Autodesk Fusion 360 part; units mm, degrees
(part 5 of 7)
equation "d238 = abs(( 0 ) * ( ( ( 1 ) * jointNodeQ * sqrt(2) - bodyWidth / 2 * cos(225 deg) + ( ( -1 ) * nodeHalfWidth ) * sin(225 deg) ) + ( 0 ) * ( ( 1 ) * endNodeX - ( ( 1 ) * jointNodeQ * sqrt(2) - bodyWidth / 2 * cos(225 deg) + ( ( -1 ) * nodeHalfWidth ) * sin(225 deg) ) ) ) + ( -1 ) * ( ( -1 ) * nodeHalfWidth ))"
equation "d239 = abs(( 1 ) * ( ( ( 1 ) * jointNodeQ * sqrt(2) - bodyWidth / 2 * cos(225 deg) + ( ( 1 ) * nodeHalfWidth ) * sin(225 deg) ) + ( 0 ) * ( ( 1 ) * endNodeX - ( ( 1 ) * jointNodeQ * sqrt(2) - bodyWidth / 2 * cos(225 deg) + ( ( 1 ) * nodeHalfWidth ) * sin(225 deg) ) ) ) + ( 0 ) * ( ( 1 ) * nodeHalfWidth ))"
equation "d240 = abs(( 0 ) * ( ( ( 1 ) * jointNodeQ * sqrt(2) - bodyWidth / 2 * cos(225 deg) + ( ( 1 ) * nodeHalfWidth ) * sin(225 deg) ) + ( 0 ) * ( ( 1 ) * endNodeX - ( ( 1 ) * jointNodeQ * sqrt(2) - bodyWidth / 2 * cos(225 deg) + ( ( 1 ) * nodeHalfWidth ) * sin(225 deg) ) ) ) + ( -1 ) * ( ( 1 ) * nodeHalfWidth ))"
equation "d241 = abs(( 1 ) * ( ( ( 1 ) * jointNodeQ * sqrt(2) - bodyWidth / 2 * cos(225 deg) + ( ( -1 ) * nodeHalfWidth ) * sin(225 deg) ) + ( 1 ) * ( ( 1 ) * endNodeX - ( ( 1 ) * jointNodeQ * sqrt(2) - bodyWidth / 2 * cos(225 deg) + ( ( -1 ) * nodeHalfWidth ) * sin(225 deg) ) ) ) + ( 0 ) * ( ( -1 ) * nodeHalfWidth ))"
equation "d242 = abs(( 0 ) * ( ( ( 1 ) * jointNodeQ * sqrt(2) - bodyWidth / 2 * cos(225 deg) + ( ( -1 ) * nodeHalfWidth ) * sin(225 deg) ) + ( 1 ) * ( ( 1 ) * endNodeX - ( ( 1 ) * jointNodeQ * sqrt(2) - bodyWidth / 2 * cos(225 deg) + ( ( -1 ) * nodeHalfWidth ) * sin(225 deg) ) ) ) + ( -1 ) * ( ( -1 ) * nodeHalfWidth ))"
equation "d243 = -memberWidth / 2"
equation "d244 = -( wall + 0.2 mm )"
equation "d246 = abs(( 1 ) * ( ( ( 1 ) * jointNodeQ * sqrt(2) - bodyWidth / 2 * cos(225 deg) + ( ( 1 ) * nodeHalfWidth ) * sin(225 deg) ) + ( 0 ) * ( ( 1 ) * endNodeX - ( ( 1 ) * jointNodeQ * sqrt(2) - bodyWidth / 2 * cos(225 deg) + ( ( 1 ) * nodeHalfWidth ) * sin(225 deg) ) ) ) + ( 0 ) * ( ( 1 ) * nodeHalfWidth ))"
equation "d247 = abs(( 0 ) * ( ( ( 1 ) * jointNodeQ * sqrt(2) - bodyWidth / 2 * cos(225 deg) + ( ( 1 ) * nodeHalfWidth ) * sin(225 deg) ) + ( 0 ) * ( ( 1 ) * endNodeX - ( ( 1 ) * jointNodeQ * sqrt(2) - bodyWidth / 2 * cos(225 deg) + ( ( 1 ) * nodeHalfWidth ) * sin(225 deg) ) ) ) + ( -1 ) * ( ( 1 ) * nodeHalfWidth ))"
equation "d248 = abs(( 1 ) * ( ( ( 1 ) * jointNodeQ * sqrt(2) - bodyWidth / 2 * cos(225 deg) + ( ( -1 ) * nodeHalfWidth ) * sin(225 deg) ) + ( 1 ) * ( ( 1 ) * endNodeX - ( ( 1 ) * jointNodeQ * sqrt(2) - bodyWidth / 2 * cos(225 deg) + ( ( -1 ) * nodeHalfWidth ) * sin(225 deg) ) ) ) + ( 0 ) * ( ( -1 ) * nodeHalfWidth ))"
equation "d249 = abs(( 0 ) * ( ( ( 1 ) * jointNodeQ * sqrt(2) - bodyWidth / 2 * cos(225 deg) + ( ( -1 ) * nodeHalfWidth ) * sin(225 deg) ) + ( 1 ) * ( ( 1 ) * endNodeX - ( ( 1 ) * jointNodeQ * sqrt(2) - bodyWidth / 2 * cos(225 deg) + ( ( -1 ) * nodeHalfWidth ) * sin(225 deg) ) ) ) + ( -1 ) * ( ( -1 ) * nodeHalfWidth ))"
equation "d250 = abs(( 1 ) * ( ( ( 1 ) * jointNodeQ * sqrt(2) - bodyWidth / 2 * cos(225 deg) + ( ( 1 ) * nodeHalfWidth ) * sin(225 deg) ) + ( 1 ) * ( ( 1 ) * endNodeX - ( ( 1 ) * jointNodeQ * sqrt(2) - bodyWidth / 2 * cos(225 deg) + ( ( 1 ) * nodeHalfWidth ) * sin(225 deg) ) ) ) + ( 0 ) * ( ( 1 ) * nodeHalfWidth ))"
equation "d251 = abs(( 0 ) * ( ( ( 1 ) * jointNodeQ * sqrt(2) - bodyWidth / 2 * cos(225 deg) + ( ( 1 ) * nodeHalfWidth ) * sin(225 deg) ) + ( 1 ) * ( ( 1 ) * endNodeX - ( ( 1 ) * jointNodeQ * sqrt(2) - bodyWidth / 2 * cos(225 deg) + ( ( 1 ) * nodeHalfWidth ) * sin(225 deg) ) ) ) + ( -1 ) * ( ( 1 ) * nodeHalfWidth ))"
equation "d252 = memberWidth / 2"
equation "d253 = -( wall + 0.2 mm )"
equation "d256 = apertureRadius"
equation "d259 = bodyWidth / 2"
equation "d261 = abs(( -1 ) * ( ( ( 1 ) * jointNodeQ * sqrt(2) - bodyWidth / 2 * cos(270 deg) + ( ( -1 ) * nodeHalfWidth ) * sin(270 deg) ) + ( 0 ) * ( ( 1 ) * endNodeX - ( ( 1 ) * jointNodeQ * sqrt(2) - bodyWidth / 2 * cos(270 deg) + ( ( -1 ) * nodeHalfWidth ) * sin(270 deg) ) ) ) + ( 0 ) * ( ( -1 ) * nodeHalfWidth ))"
equation "d262 = abs(( 0 ) * ( ( ( 1 ) * jointNodeQ * sqrt(2) - bodyWidth / 2 * cos(270 deg) + ( ( -1 ) * nodeHalfWidth ) * sin(270 deg) ) + ( 0 ) * ( ( 1 ) * endNodeX - ( ( 1 ) * jointNodeQ * sqrt(2) - bodyWidth / 2 * cos(270 deg) + ( ( -1 ) * nodeHalfWidth ) * sin(270 deg) ) ) ) + ( 1 ) * ( ( -1 ) * nodeHalfWidth ))"
equation "d263 = abs(( -1 ) * ( ( ( 1 ) * jointNodeQ * sqrt(2) - bodyWidth / 2 * cos(270 deg) + ( ( 1 ) * nodeHalfWidth ) * sin(270 deg) ) + ( 0 ) * ( ( 1 ) * endNodeX - ( ( 1 ) * jointNodeQ * sqrt(2) - bodyWidth / 2 * cos(270 deg) + ( ( 1 ) * nodeHalfWidth ) * sin(270 deg) ) ) ) + ( 0 ) * ( ( 1 ) * nodeHalfWidth ))"
equation "d264 = abs(( 0 ) * ( ( ( 1 ) * jointNodeQ * sqrt(2) - bodyWidth / 2 * cos(270 deg) + ( ( 1 ) * nodeHalfWidth ) * sin(270 deg) ) + ( 0 ) * ( ( 1 ) * endNodeX - ( ( 1 ) * jointNodeQ * sqrt(2) - bodyWidth / 2 * cos(270 deg) + ( ( 1 ) * nodeHalfWidth ) * sin(270 deg) ) ) ) + ( 1 ) * ( ( 1 ) * nodeHalfWidth ))"
equation "d265 = abs(( -1 ) * ( ( ( 1 ) * jointNodeQ * sqrt(2) - bodyWidth / 2 * cos(270 deg) + ( ( -1 ) * nodeHalfWidth ) * sin(270 deg) ) + ( 0.5 ) * ( ( 1 ) * endNodeX - ( ( 1 ) * jointNodeQ * sqrt(2) - bodyWidth / 2 * cos(270 deg) + ( ( -1 ) * nodeHalfWidth ) * sin(270 deg) ) ) ) + ( 0 ) * ( ( -1 ) * nodeHalfWidth ))"
equation "d266 = abs(( 0 ) * ( ( ( 1 ) * jointNodeQ * sqrt(2) - bodyWidth / 2 * cos(270 deg) + ( ( -1 ) * nodeHalfWidth ) * sin(270 deg) ) + ( 0.5 ) * ( ( 1 ) * endNodeX - ( ( 1 ) * jointNodeQ * sqrt(2) - bodyWidth / 2 * cos(270 deg) + ( ( -1 ) * nodeHalfWidth ) * sin(270 deg) ) ) ) + ( 1 ) * ( ( -1 ) * nodeHalfWidth ))"
equation "d267 = -memberWidth / 2"
equation "d268 = -( wall + 0.2 mm )"
equation "d270 = abs(( -1 ) * ( ( ( 1 ) * jointNodeQ * sqrt(2) - bodyWidth / 2 * cos(270 deg) + ( ( 1 ) * nodeHalfWidth ) * sin(270 deg) ) + ( 0 ) * ( ( 1 ) * endNodeX - ( ( 1 ) * jointNodeQ * sqrt(2) - bodyWidth / 2 * cos(270 deg) + ( ( 1 ) * nodeHalfWidth ) * sin(270 deg) ) ) ) + ( 0 ) * ( ( 1 ) * nodeHalfWidth ))"
equation "d271 = abs(( 0 ) * ( ( ( 1 ) * jointNodeQ * sqrt(2) - bodyWidth / 2 * cos(270 deg) + ( ( 1 ) * nodeHalfWidth ) * sin(270 deg) ) + ( 0 ) * ( ( 1 ) * endNodeX - ( ( 1 ) * jointNodeQ * sqrt(2) - bodyWidth / 2 * cos(270 deg) + ( ( 1 ) * nodeHalfWidth ) * sin(270 deg) ) ) ) + ( 1 ) * ( ( 1 ) * nodeHalfWidth ))"
equation "d272 = abs(( -1 ) * ( ( ( 1 ) * jointNodeQ * sqrt(2) - bodyWidth / 2 * cos(270 deg) + ( ( -1 ) * nodeHalfWidth ) * sin(270 deg) ) + ( 0.5 ) * ( ( 1 ) * endNodeX - ( ( 1 ) * jointNodeQ * sqrt(2) - bodyWidth / 2 * cos(270 deg) + ( ( -1 ) * nodeHalfWidth ) * sin(270 deg) ) ) ) + ( 0 ) * ( ( -1 ) * nodeHalfWidth ))"
equation "d273 = abs(( 0 ) * ( ( ( 1 ) * jointNodeQ * sqrt(2) - bodyWidth / 2 * cos(270 deg) + ( ( -1 ) * nodeHalfWidth ) * sin(270 deg) ) + ( 0.5 ) * ( ( 1 ) * endNodeX - ( ( 1 ) * jointNodeQ * sqrt(2) - bodyWidth / 2 * cos(270 deg) + ( ( -1 ) * nodeHalfWidth ) * sin(270 deg) ) ) ) + ( 1 ) * ( ( -1 ) * nodeHalfWidth ))"
equation "d274 = abs(( -1 ) * ( ( ( 1 ) * jointNodeQ * sqrt(2) - bodyWidth / 2 * cos(270 deg) + ( ( 1 ) * nodeHalfWidth ) * sin(270 deg) ) + ( 1 ) * ( ( 1 ) * endNodeX - ( ( 1 ) * jointNodeQ * sqrt(2) - bodyWidth / 2 * cos(270 deg) + ( ( 1 ) * nodeHalfWidth ) * sin(270 deg) ) ) ) + ( 0 ) * ( ( 1 ) * nodeHalfWidth ))"
equation "d275 = abs(( 0 ) * ( ( ( 1 ) * jointNodeQ * sqrt(2) - bodyWidth / 2 * cos(270 deg) + ( ( 1 ) * nodeHalfWidth ) * sin(270 deg) ) + ( 1 ) * ( ( 1 ) * endNodeX - ( ( 1 ) * jointNodeQ * sqrt(2) - bodyWidth / 2 * cos(270 deg) + ( ( 1 ) * nodeHalfWidth ) * sin(270 deg) ) ) ) + ( 1 ) * ( ( 1 ) * nodeHalfWidth ))"
equation "d276 = memberWidth / 2"
equation "d277 = -( wall + 0.2 mm )"
equation "d279 = abs(( -1 ) * ( ( ( 1 ) * jointNodeQ * sqrt(2) - bodyWidth / 2 * cos(270 deg) + ( ( -1 ) * nodeHalfWidth ) * sin(270 deg) ) + ( 0.5 ) * ( ( 1 ) * endNodeX - ( ( 1 ) * jointNodeQ * sqrt(2) - bodyWidth / 2 * cos(270 deg) + ( ( -1 ) * nodeHalfWidth ) * sin(270 deg) ) ) ) + ( 0 ) * ( ( -1 ) * nodeHalfWidth ))"
equation "d280 = abs(( 0 ) * ( ( ( 1 ) * jointNodeQ * sqrt(2) - bodyWidth / 2 * cos(270 deg) + ( ( -1 ) * nodeHalfWidth ) * sin(270 deg) ) + ( 0.5 ) * ( ( 1 ) * endNodeX - ( ( 1 ) * jointNodeQ * sqrt(2) - bodyWidth / 2 * cos(270 deg) + ( ( -1 ) * nodeHalfWidth ) * sin(270 deg) ) ) ) + ( 1 ) * ( ( -1 ) * nodeHalfWidth ))"
equation "d281 = abs(( -1 ) * ( ( ( 1 ) * jointNodeQ * sqrt(2) - bodyWidth / 2 * cos(270 deg) + ( ( 1 ) * nodeHalfWidth ) * sin(270 deg) ) + ( 1 ) * ( ( 1 ) * endNodeX - ( ( 1 ) * jointNodeQ * sqrt(2) - bodyWidth / 2 * cos(270 deg) + ( ( 1 ) * nodeHalfWidth ) * sin(270 deg) ) ) ) + ( 0 ) * ( ( 1 ) * nodeHalfWidth ))"
equation "d282 = abs(( 0 ) * ( ( ( 1 ) * jointNodeQ * sqrt(2) - bodyWidth / 2 * cos(270 deg) + ( ( 1 ) * nodeHalfWidth ) * sin(270 deg) ) + ( 1 ) * ( ( 1 ) * endNodeX - ( ( 1 ) * jointNodeQ * sqrt(2) - bodyWidth / 2 * cos(270 deg) + ( ( 1 ) * nodeHalfWidth ) * sin(270 deg) ) ) ) + ( 1 ) * ( ( 1 ) * nodeHalfWidth ))"
equation "d283 = abs(( -1 ) * ( ( ( 1 ) * jointNodeQ * sqrt(2) - bodyWidth / 2 * cos(270 deg) + ( ( -1 ) * nodeHalfWidth ) * sin(270 deg) ) + ( 1 ) * ( ( 1 ) * endNodeX - ( ( 1 ) * jointNodeQ * sqrt(2) - bodyWidth / 2 * cos(270 deg) + ( ( -1 ) * nodeHalfWidth ) * sin(270 deg) ) ) ) + ( 0 ) * ( ( -1 ) * nodeHalfWidth ))"
equation "d284 = abs(( 0 ) * ( ( ( 1 ) * jointNodeQ * sqrt(2) - bodyWidth / 2 * cos(270 deg) + ( ( -1 ) * nodeHalfWidth ) * sin(270 deg) ) + ( 1 ) * ( ( 1 ) * endNodeX - ( ( 1 ) * jointNodeQ * sqrt(2) - bodyWidth / 2 * cos(270 deg) + ( ( -1 ) * nodeHalfWidth ) * sin(270 deg) ) ) ) + ( 1 ) * ( ( -1 ) * nodeHalfWidth ))"
equation "d285 = -memberWidth / 2"
equation "d286 = -( wall + 0.2 mm )"
equation "d289 = apertureRadius"
equation "d292 = bodyWidth / 2"
equation "d294 = abs(( 1 ) * ( ( ( 1 ) * jointNodeQ * sqrt(2) - bodyWidth / 2 * cos(315 deg) + ( ( -1 ) * nodeHalfWidth ) * sin(315 deg) ) + ( 0 ) * ( ( 1 ) * endNodeX - ( ( 1 ) * jointNodeQ * sqrt(2) - bodyWidth / 2 * cos(315 deg) + ( ( -1 ) * nodeHalfWidth ) * sin(315 deg) ) ) ) + ( 0 ) * ( ( -1 ) * nodeHalfWidth ))"
equation "d295 = abs(( 0 ) * ( ( ( 1 ) * jointNodeQ * sqrt(2) - bodyWidth / 2 * cos(315 deg) + ( ( -1 ) * nodeHalfWidth ) * sin(315 deg) ) + ( 0 ) * ( ( 1 ) * endNodeX - ( ( 1 ) * jointNodeQ * sqrt(2) - bodyWidth / 2 * cos(315 deg) + ( ( -1 ) * nodeHalfWidth ) * sin(315 deg) ) ) ) + ( -1 ) * ( ( -1 ) * nodeHalfWidth ))"
equation "d296 = abs(( 1 ) * ( ( ( 1 ) * jointNodeQ * sqrt(2) - bodyWidth / 2 * cos(315 deg) + ( ( 1 ) * nodeHalfWidth ) * sin(315 deg) ) + ( 0 ) * ( ( 1 ) * endNodeX - ( ( 1 ) * jointNodeQ * sqrt(2) - bodyWidth / 2 * cos(315 deg) + ( ( 1 ) * nodeHalfWidth ) * sin(315 deg) ) ) ) + ( 0 ) * ( ( 1 ) * nodeHalfWidth ))"
equation "d297 = abs(( 0 ) * ( ( ( 1 ) * jointNodeQ * sqrt(2) - bodyWidth / 2 * cos(315 deg) + ( ( 1 ) * nodeHalfWidth ) * sin(315 deg) ) + ( 0 ) * ( ( 1 ) * endNodeX - ( ( 1 ) * jointNodeQ * sqrt(2) - bodyWidth / 2 * cos(315 deg) + ( ( 1 ) * nodeHalfWidth ) * sin(315 deg) ) ) ) + ( -1 ) * ( ( 1 ) * nodeHalfWidth ))"
equation "d298 = abs(( 1 ) * ( ( ( 1 ) * jointNodeQ * sqrt(2) - bodyWidth / 2 * cos(315 deg) + ( ( -1 ) * nodeHalfWidth ) * sin(315 deg) ) + ( 0.333333333333333 ) * ( ( 1 ) * endNodeX - ( ( 1 ) * jointNodeQ * sqrt(2) - bodyWidth / 2 * cos(315 deg) + ( ( -1 ) * nodeHalfWidth ) * sin(315 deg) ) ) ) + ( 0 ) * ( ( -1 ) * nodeHalfWidth ))"
equation "d299 = abs(( 0 ) * ( ( ( 1 ) * jointNodeQ * sqrt(2) - bodyWidth / 2 * cos(315 deg) + ( ( -1 ) * nodeHalfWidth ) * sin(315 deg) ) + ( 0.333333333333333 ) * ( ( 1 ) * endNodeX - ( ( 1 ) * jointNodeQ * sqrt(2) - bodyWidth / 2 * cos(315 deg) + ( ( -1 ) * nodeHalfWidth ) * sin(315 deg) ) ) ) + ( -1 ) * ( ( -1 ) * nodeHalfWidth ))"
equation "d300 = -memberWidth / 2"
equation "d301 = -( wall + 0.2 mm )"
equation "d303 = abs(( 1 ) * ( ( ( 1 ) * jointNodeQ * sqrt(2) - bodyWidth / 2 * cos(315 deg) + ( ( 1 ) * nodeHalfWidth ) * sin(315 deg) ) + ( 0 ) * ( ( 1 ) * endNodeX - ( ( 1 ) * jointNodeQ * sqrt(2) - bodyWidth / 2 * cos(315 deg) + ( ( 1 ) * nodeHalfWidth ) * sin(315 deg) ) ) ) + ( 0 ) * ( ( 1 ) * nodeHalfWidth ))"
equation "d304 = abs(( 0 ) * ( ( ( 1 ) * jointNodeQ * sqrt(2) - bodyWidth / 2 * cos(315 deg) + ( ( 1 ) * nodeHalfWidth ) * sin(315 deg) ) + ( 0 ) * ( ( 1 ) * endNodeX - ( ( 1 ) * jointNodeQ * sqrt(2) - bodyWidth / 2 * cos(315 deg) + ( ( 1 ) * nodeHalfWidth ) * sin(315 deg) ) ) ) + ( -1 ) * ( ( 1 ) * nodeHalfWidth ))"
equation "d305 = abs(( 1 ) * ( ( ( 1 ) * jointNodeQ * sqrt(2) - bodyWidth / 2 * cos(315 deg) + ( ( -1 ) * nodeHalfWidth ) * sin(315 deg) ) + ( 0.333333333333333 ) * ( ( 1 ) * endNodeX - ( ( 1 ) * jointNodeQ * sqrt(2) - bodyWidth / 2 * cos(315 deg) + ( ( -1 ) * nodeHalfWidth ) * sin(315 deg) ) ) ) + ( 0 ) * ( ( -1 ) * nodeHalfWidth ))"
equation "d306 = abs(( 0 ) * ( ( ( 1 ) * jointNodeQ * sqrt(2) - bodyWidth / 2 * cos(315 deg) + ( ( -1 ) * nodeHalfWidth ) * sin(315 deg) ) + ( 0.333333333333333 ) * ( ( 1 ) * endNodeX - ( ( 1 ) * jointNodeQ * sqrt(2) - bodyWidth / 2 * cos(315 deg) + ( ( -1 ) * nodeHalfWidth ) * sin(315 deg) ) ) ) + ( -1 ) * ( ( -1 ) * nodeHalfWidth ))"
equation "d307 = abs(( 1 ) * ( ( ( 1 ) * jointNodeQ * sqrt(2) - bodyWidth / 2 * cos(315 deg) + ( ( 1 ) * nodeHalfWidth ) * sin(315 deg) ) + ( 0.666666666666667 ) * ( ( 1 ) * endNodeX - ( ( 1 ) * jointNodeQ * sqrt(2) - bodyWidth / 2 * cos(315 deg) + ( ( 1 ) * nodeHalfWidth ) * sin(315 deg) ) ) ) + ( 0 ) * ( ( 1 ) * nodeHalfWidth ))"
equation "d308 = abs(( 0 ) * ( ( ( 1 ) * jointNodeQ * sqrt(2) - bodyWidth / 2 * cos(315 deg) + ( ( 1 ) * nodeHalfWidth ) * sin(315 deg) ) + ( 0.666666666666667 ) * ( ( 1 ) * endNodeX - ( ( 1 ) * jointNodeQ * sqrt(2) - bodyWidth / 2 * cos(315 deg) + ( ( 1 ) * nodeHalfWidth ) * sin(315 deg) ) ) ) + ( -1 ) * ( ( 1 ) * nodeHalfWidth ))"
equation "d309 = memberWidth / 2"
equation "d310 = -( wall + 0.2 mm )"
equation "d312 = abs(( 1 ) * ( ( ( 1 ) * jointNodeQ * sqrt(2) - bodyWidth / 2 * cos(315 deg) + ( ( -1 ) * nodeHalfWidth ) * sin(315 deg) ) + ( 0.333333333333333 ) * ( ( 1 ) * endNodeX - ( ( 1 ) * jointNodeQ * sqrt(2) - bodyWidth / 2 * cos(315 deg) + ( ( -1 ) * nodeHalfWidth ) * sin(315 deg) ) ) ) + ( 0 ) * ( ( -1 ) * nodeHalfWidth ))"
equation "d313 = abs(( 0 ) * ( ( ( 1 ) * jointNodeQ * sqrt(2) - bodyWidth / 2 * cos(315 deg) + ( ( -1 ) * nodeHalfWidth ) * sin(315 deg) ) + ( 0.333333333333333 ) * ( ( 1 ) * endNodeX - ( ( 1 ) * jointNodeQ * sqrt(2) - bodyWidth / 2 * cos(315 deg) + ( ( -1 ) * nodeHalfWidth ) * sin(315 deg) ) ) ) + ( -1 ) * ( ( -1 ) * nodeHalfWidth ))"
equation "d314 = abs(( 1 ) * ( ( ( 1 ) * jointNodeQ * sqrt(2) - bodyWidth / 2 * cos(315 deg) + ( ( 1 ) * nodeHalfWidth ) * sin(315 deg) ) + ( 0.666666666666667 ) * ( ( 1 ) * endNodeX - ( ( 1 ) * jointNodeQ * sqrt(2) - bodyWidth / 2 * cos(315 deg) + ( ( 1 ) * nodeHalfWidth ) * sin(315 deg) ) ) ) + ( 0 ) * ( ( 1 ) * nodeHalfWidth ))"
equation "d315 = abs(( 0 ) * ( ( ( 1 ) * jointNodeQ * sqrt(2) - bodyWidth / 2 * cos(315 deg) + ( ( 1 ) * nodeHalfWidth ) * sin(315 deg) ) + ( 0.666666666666667 ) * ( ( 1 ) * endNodeX - ( ( 1 ) * jointNodeQ * sqrt(2) - bodyWidth / 2 * cos(315 deg) + ( ( 1 ) * nodeHalfWidth ) * sin(315 deg) ) ) ) + ( -1 ) * ( ( 1 ) * nodeHalfWidth ))"
equation "d316 = abs(( 1 ) * ( ( ( 1 ) * jointNodeQ * sqrt(2) - bodyWidth / 2 * cos(315 deg) + ( ( -1 ) * nodeHalfWidth ) * sin(315 deg) ) + ( 1 ) * ( ( 1 ) * endNodeX - ( ( 1 ) * jointNodeQ * sqrt(2) - bodyWidth / 2 * cos(315 deg) + ( ( -1 ) * nodeHalfWidth ) * sin(315 deg) ) ) ) + ( 0 ) * ( ( -1 ) * nodeHalfWidth ))"
equation "d317 = abs(( 0 ) * ( ( ( 1 ) * jointNodeQ * sqrt(2) - bodyWidth / 2 * cos(315 deg) + ( ( -1 ) * nodeHalfWidth ) * sin(315 deg) ) + ( 1 ) * ( ( 1 ) * endNodeX - ( ( 1 ) * jointNodeQ * sqrt(2) - bodyWidth / 2 * cos(315 deg) + ( ( -1 ) * nodeHalfWidth ) * sin(315 deg) ) ) ) + ( -1 ) * ( ( -1 ) * nodeHalfWidth ))"
equation "d318 = -memberWidth / 2"
equation "d319 = -( wall + 0.2 mm )"
equation "d321 = abs(( 1 ) * ( ( ( 1 ) * jointNodeQ * sqrt(2) - bodyWidth / 2 * cos(315 deg) + ( ( 1 ) * nodeHalfWidth ) * sin(315 deg) ) + ( 0.666666666666667 ) * ( ( 1 ) * endNodeX - ( ( 1 ) * jointNodeQ * sqrt(2) - bodyWidth / 2 * cos(315 deg) + ( ( 1 ) * nodeHalfWidth ) * sin(315 deg) ) ) ) + ( 0 ) * ( ( 1 ) * nodeHalfWidth ))"
equation "d322 = abs(( 0 ) * ( ( ( 1 ) * jointNodeQ * sqrt(2) - bodyWidth / 2 * cos(315 deg) + ( ( 1 ) * nodeHalfWidth ) * sin(315 deg) ) + ( 0.666666666666667 ) * ( ( 1 ) * endNodeX - ( ( 1 ) * jointNodeQ * sqrt(2) - bodyWidth / 2 * cos(315 deg) + ( ( 1 ) * nodeHalfWidth ) * sin(315 deg) ) ) ) + ( -1 ) * ( ( 1 ) * nodeHalfWidth ))"
equation "d323 = abs(( 1 ) * ( ( ( 1 ) * jointNodeQ * sqrt(2) - bodyWidth / 2 * cos(315 deg) + ( ( -1 ) * nodeHalfWidth ) * sin(315 deg) ) + ( 1 ) * ( ( 1 ) * endNodeX - ( ( 1 ) * jointNodeQ * sqrt(2) - bodyWidth / 2 * cos(315 deg) + ( ( -1 ) * nodeHalfWidth ) * sin(315 deg) ) ) ) + ( 0 ) * ( ( -1 ) * nodeHalfWidth ))"
equation "d324 = abs(( 0 ) * ( ( ( 1 ) * jointNodeQ * sqrt(2) - bodyWidth / 2 * cos(315 deg) + ( ( -1 ) * nodeHalfWidth ) * sin(315 deg) ) + ( 1 ) * ( ( 1 ) * endNodeX - ( ( 1 ) * jointNodeQ * sqrt(2) - bodyWidth / 2 * cos(315 deg) + ( ( -1 ) * nodeHalfWidth ) * sin(315 deg) ) ) ) + ( -1 ) * ( ( -1 ) * nodeHalfWidth ))"
equation "d325 = abs(( 1 ) * ( ( ( 1 ) * jointNodeQ * sqrt(2) - bodyWidth / 2 * cos(315 deg) + ( ( 1 ) * nodeHalfWidth ) * sin(315 deg) ) + ( 1 ) * ( ( 1 ) * endNodeX - ( ( 1 ) * jointNodeQ * sqrt(2) - bodyWidth / 2 * cos(315 deg) + ( ( 1 ) * nodeHalfWidth ) * sin(315 deg) ) ) ) + ( 0 ) * ( ( 1 ) * nodeHalfWidth ))"
equation "d326 = abs(( 0 ) * ( ( ( 1 ) * jointNodeQ * sqrt(2) - bodyWidth / 2 * cos(315 deg) + ( ( 1 ) * nodeHalfWidth ) * sin(315 deg) ) + ( 1 ) * ( ( 1 ) * endNodeX - ( ( 1 ) * jointNodeQ * sqrt(2) - bodyWidth / 2 * cos(315 deg) + ( ( 1 ) * nodeHalfWidth ) * sin(315 deg) ) ) ) + ( -1 ) * ( ( 1 ) * nodeHalfWidth ))"
equation "d327 = memberWidth / 2"
equation "d328 = -( wall + 0.2 mm )"
equation "d331 = apertureRadius"
equation "d334 = bodyWidth / 2"
equation "d336 = abs(( 1 ) * ( ( ( -1 ) * jointNodeQ * sqrt(2) - bodyWidth / 2 * cos(0 deg) + ( ( -1 ) * nodeHalfWidth ) * sin(0 deg) ) + ( 0 ) * ( ( -1 ) * endNodeX - ( ( -1 ) * jointNodeQ * sqrt(2) - bodyWidth / 2 * cos(0 deg) + ( ( -1 ) * nodeHalfWidth ) * sin(0 deg) ) ) ) + ( 0 ) * ( ( -1 ) * nodeHalfWidth ))"
equation "d337 = abs(( 0 ) * ( ( ( -1 ) * jointNodeQ * sqrt(2) - bodyWidth / 2 * cos(0 deg) + ( ( -1 ) * nodeHalfWidth ) * sin(0 deg) ) + ( 0 ) * ( ( -1 ) * endNodeX - ( ( -1 ) * jointNodeQ * sqrt(2) - bodyWidth / 2 * cos(0 deg) + ( ( -1 ) * nodeHalfWidth ) * sin(0 deg) ) ) ) + ( -1 ) * ( ( -1 ) * nodeHalfWidth ))"
equation "d338 = abs(( 1 ) * ( ( ( -1 ) * jointNodeQ * sqrt(2) - bodyWidth / 2 * cos(0 deg) + ( ( 1 ) * nodeHalfWidth ) * sin(0 deg) ) + ( 0 ) * ( ( -1 ) * endNodeX - ( ( -1 ) * jointNodeQ * sqrt(2) - bodyWidth / 2 * cos(0 deg) + ( ( 1 ) * nodeHalfWidth ) * sin(0 deg) ) ) ) + ( 0 ) * ( ( 1 ) * nodeHalfWidth ))"
equation "d339 = abs(( 0 ) * ( ( ( -1 ) * jointNodeQ * sqrt(2) - bodyWidth / 2 * cos(0 deg) + ( ( 1 ) * nodeHalfWidth ) * sin(0 deg) ) + ( 0 ) * ( ( -1 ) * endNodeX - ( ( -1 ) * jointNodeQ * sqrt(2) - bodyWidth / 2 * cos(0 deg) + ( ( 1 ) * nodeHalfWidth ) * sin(0 deg) ) ) ) + ( -1 ) * ( ( 1 ) * nodeHalfWidth ))"
equation "d340 = abs(( 1 ) * ( ( ( -1 ) * jointNodeQ * sqrt(2) - bodyWidth / 2 * cos(0 deg) + ( ( -1 ) * nodeHalfWidth ) * sin(0 deg) ) + ( 1 ) * ( ( -1 ) * endNodeX - ( ( -1 ) * jointNodeQ * sqrt(2) - bodyWidth / 2 * cos(0 deg) + ( ( -1 ) * nodeHalfWidth ) * sin(0 deg) ) ) ) + ( 0 ) * ( ( -1 ) * nodeHalfWidth ))"
equation "d341 = abs(( 0 ) * ( ( ( -1 ) * jointNodeQ * sqrt(2) - bodyWidth / 2 * cos(0 deg) + ( ( -1 ) * nodeHalfWidth ) * sin(0 deg) ) + ( 1 ) * ( ( -1 ) * endNodeX - ( ( -1 ) * jointNodeQ * sqrt(2) - bodyWidth / 2 * cos(0 deg) + ( ( -1 ) * nodeHalfWidth ) * sin(0 deg) ) ) ) + ( -1 ) * ( ( -1 ) * nodeHalfWidth ))"
equation "d342 = memberWidth / 2"
equation "d343 = -( wall + 0.2 mm )"
equation "d345 = abs(( 1 ) * ( ( ( -1 ) * jointNodeQ * sqrt(2) - bodyWidth / 2 * cos(0 deg) + ( ( 1 ) * nodeHalfWidth ) * sin(0 deg) ) + ( 0 ) * ( ( -1 ) * endNodeX - ( ( -1 ) * jointNodeQ * sqrt(2) - bodyWidth / 2 * cos(0 deg) + ( ( 1 ) * nodeHalfWidth ) * sin(0 deg) ) ) ) + ( 0 ) * ( ( 1 ) * nodeHalfWidth ))"
equation "d346 = abs(( 0 ) * ( ( ( -1 ) * jointNodeQ * sqrt(2) - bodyWidth / 2 * cos(0 deg) + ( ( 1 ) * nodeHalfWidth ) * sin(0 deg) ) + ( 0 ) * ( ( -1 ) * endNodeX - ( ( -1 ) * jointNodeQ * sqrt(2) - bodyWidth / 2 * cos(0 deg) + ( ( 1 ) * nodeHalfWidth ) * sin(0 deg) ) ) ) + ( -1 ) * ( ( 1 ) * nodeHalfWidth ))"
equation "d347 = abs(( 1 ) * ( ( ( -1 ) * jointNodeQ * sqrt(2) - bodyWidth / 2 * cos(0 deg) + ( ( -1 ) * nodeHalfWidth ) * sin(0 deg) ) + ( 1 ) * ( ( -1 ) * endNodeX - ( ( -1 ) * jointNodeQ * sqrt(2) - bodyWidth / 2 * cos(0 deg) + ( ( -1 ) * nodeHalfWidth ) * sin(0 deg) ) ) ) + ( 0 ) * ( ( -1 ) * nodeHalfWidth ))"
equation "d348 = abs(( 0 ) * ( ( ( -1 ) * jointNodeQ * sqrt(2) - bodyWidth / 2 * cos(0 deg) + ( ( -1 ) * nodeHalfWidth ) * sin(0 deg) ) + ( 1 ) * ( ( -1 ) * endNodeX - ( ( -1 ) * jointNodeQ * sqrt(2) - bodyWidth / 2 * cos(0 deg) + ( ( -1 ) * nodeHalfWidth ) * sin(0 deg) ) ) ) + ( -1 ) * ( ( -1 ) * nodeHalfWidth ))"
equation "d349 = abs(( 1 ) * ( ( ( -1 ) * jointNodeQ * sqrt(2) - bodyWidth / 2 * cos(0 deg) + ( ( 1 ) * nodeHalfWidth ) * sin(0 deg) ) + ( 1 ) * ( ( -1 ) * endNodeX - ( ( -1 ) * jointNodeQ * sqrt(2) - bodyWidth / 2 * cos(0 deg) + ( ( 1 ) * nodeHalfWidth ) * sin(0 deg) ) ) ) + ( 0 ) * ( ( 1 ) * nodeHalfWidth ))"
equation "d350 = abs(( 0 ) * ( ( ( -1 ) * jointNodeQ * sqrt(2) - bodyWidth / 2 * cos(0 deg) + ( ( 1 ) * nodeHalfWidth ) * sin(0 deg) ) + ( 1 ) * ( ( -1 ) * endNodeX - ( ( -1 ) * jointNodeQ * sqrt(2) - bodyWidth / 2 * cos(0 deg) + ( ( 1 ) * nodeHalfWidth ) * sin(0 deg) ) ) ) + ( -1 ) * ( ( 1 ) * nodeHalfWidth ))"
equation "d351 = -memberWidth / 2"
equation "d352 = -( wall + 0.2 mm )"
equation "d355 = apertureRadius"
equation "d358 = bodyWidth / 2"
equation "d360 = abs(( 1 ) * ( ( ( -1 ) * jointNodeQ * sqrt(2) - bodyWidth / 2 * cos(45 deg) + ( ( -1 ) * nodeHalfWidth ) * sin(45 deg) ) + ( 0 ) * ( ( -1 ) * endNodeX - ( ( -1 ) * jointNodeQ * sqrt(2) - bodyWidth / 2 * cos(45 deg) + ( ( -1 ) * nodeHalfWidth ) * sin(45 deg) ) ) ) + ( 0 ) * ( ( -1 ) * nodeHalfWidth ))"
equation "d361 = abs(( 0 ) * ( ( ( -1 ) * jointNodeQ * sqrt(2) - bodyWidth / 2 * cos(45 deg) + ( ( -1 ) * nodeHalfWidth ) * sin(45 deg) ) + ( 0 ) * ( ( -1 ) * endNodeX - ( ( -1 ) * jointNodeQ * sqrt(2) - bodyWidth / 2 * cos(45 deg) + ( ( -1 ) * nodeHalfWidth ) * sin(45 deg) ) ) ) + ( -1 ) * ( ( -1 ) * nodeHalfWidth ))"
equation "d362 = abs(( 1 ) * ( ( ( -1 ) * jointNodeQ * sqrt(2) - bodyWidth / 2 * cos(45 deg) + ( ( 1 ) * nodeHalfWidth ) * sin(45 deg) ) + ( 0 ) * ( ( -1 ) * endNodeX - ( ( -1 ) * jointNodeQ * sqrt(2) - bodyWidth / 2 * cos(45 deg) + ( ( 1 ) * nodeHalfWidth ) * sin(45 deg) ) ) ) + ( 0 ) * ( ( 1 ) * nodeHalfWidth ))"
equation "d363 = abs(( 0 ) * ( ( ( -1 ) * jointNodeQ * sqrt(2) - bodyWidth / 2 * cos(45 deg) + ( ( 1 ) * nodeHalfWidth ) * sin(45 deg) ) + ( 0 ) * ( ( -1 ) * endNodeX - ( ( -1 ) * jointNodeQ * sqrt(2) - bodyWidth / 2 * cos(45 deg) + ( ( 1 ) * nodeHalfWidth ) * sin(45 deg) ) ) ) + ( -1 ) * ( ( 1 ) * nodeHalfWidth ))"
equation "d364 = abs(( 1 ) * ( ( ( -1 ) * jointNodeQ * sqrt(2) - bodyWidth / 2 * cos(45 deg) + ( ( -1 ) * nodeHalfWidth ) * sin(45 deg) ) + ( 1 ) * ( ( -1 ) * endNodeX - ( ( -1 ) * jointNodeQ * sqrt(2) - bodyWidth / 2 * cos(45 deg) + ( ( -1 ) * nodeHalfWidth ) * sin(45 deg) ) ) ) + ( 0 ) * ( ( -1 ) * nodeHalfWidth ))"
equation "d365 = abs(( 0 ) * ( ( ( -1 ) * jointNodeQ * sqrt(2) - bodyWidth / 2 * cos(45 deg) + ( ( -1 ) * nodeHalfWidth ) * sin(45 deg) ) + ( 1 ) * ( ( -1 ) * endNodeX - ( ( -1 ) * jointNodeQ * sqrt(2) - bodyWidth / 2 * cos(45 deg) + ( ( -1 ) * nodeHalfWidth ) * sin(45 deg) ) ) ) + ( -1 ) * ( ( -1 ) * nodeHalfWidth ))"
equation "d366 = memberWidth / 2"
equation "d367 = -( wall + 0.2 mm )"
equation "d369 = abs(( 1 ) * ( ( ( -1 ) * jointNodeQ * sqrt(2) - bodyWidth / 2 * cos(45 deg) + ( ( 1 ) * nodeHalfWidth ) * sin(45 deg) ) + ( 0 ) * ( ( -1 ) * endNodeX - ( ( -1 ) * jointNodeQ * sqrt(2) - bodyWidth / 2 * cos(45 deg) + ( ( 1 ) * nodeHalfWidth ) * sin(45 deg) ) ) ) + ( 0 ) * ( ( 1 ) * nodeHalfWidth ))"
equation "d370 = abs(( 0 ) * ( ( ( -1 ) * jointNodeQ * sqrt(2) - bodyWidth / 2 * cos(45 deg) + ( ( 1 ) * nodeHalfWidth ) * sin(45 deg) ) + ( 0 ) * ( ( -1 ) * endNodeX - ( ( -1 ) * jointNodeQ * sqrt(2) - bodyWidth / 2 * cos(45 deg) + ( ( 1 ) * nodeHalfWidth ) * sin(45 deg) ) ) ) + ( -1 ) * ( ( 1 ) * nodeHalfWidth ))"
equation "d371 = abs(( 1 ) * ( ( ( -1 ) * jointNodeQ * sqrt(2) - bodyWidth / 2 * cos(45 deg) + ( ( -1 ) * nodeHalfWidth ) * sin(45 deg) ) + ( 1 ) * ( ( -1 ) * endNodeX - ( ( -1 ) * jointNodeQ * sqrt(2) - bodyWidth / 2 * cos(45 deg) + ( ( -1 ) * nodeHalfWidth ) * sin(45 deg) ) ) ) + ( 0 ) * ( ( -1 ) * nodeHalfWidth ))"
equation "d372 = abs(( 0 ) * ( ( ( -1 ) * jointNodeQ * sqrt(2) - bodyWidth / 2 * cos(45 deg) + ( ( -1 ) * nodeHalfWidth ) * sin(45 deg) ) + ( 1 ) * ( ( -1 ) * endNodeX - ( ( -1 ) * jointNodeQ * sqrt(2) - bodyWidth / 2 * cos(45 deg) + ( ( -1 ) * nodeHalfWidth ) * sin(45 deg) ) ) ) + ( -1 ) * ( ( -1 ) * nodeHalfWidth ))"
equation "d373 = abs(( 1 ) * ( ( ( -1 ) * jointNodeQ * sqrt(2) - bodyWidth / 2 * cos(45 deg) + ( ( 1 ) * nodeHalfWidth ) * sin(45 deg) ) + ( 1 ) * ( ( -1 ) * endNodeX - ( ( -1 ) * jointNodeQ * sqrt(2) - bodyWidth / 2 * cos(45 deg) + ( ( 1 ) * nodeHalfWidth ) * sin(45 deg) ) ) ) + ( 0 ) * ( ( 1 ) * nodeHalfWidth ))"
equation "d374 = abs(( 0 ) * ( ( ( -1 ) * jointNodeQ * sqrt(2) - bodyWidth / 2 * cos(45 deg) + ( ( 1 ) * nodeHalfWidth ) * sin(45 deg) ) + ( 1 ) * ( ( -1 ) * endNodeX - ( ( -1 ) * jointNodeQ * sqrt(2) - bodyWidth / 2 * cos(45 deg) + ( ( 1 ) * nodeHalfWidth ) * sin(45 deg) ) ) ) + ( -1 ) * ( ( 1 ) * nodeHalfWidth ))"
equation "d375 = -memberWidth / 2"
equation "d376 = -( wall + 0.2 mm )"
equation "d379 = apertureRadius"
equation "d382 = bodyWidth / 2"
equation "d384 = abs(( 1 ) * ( ( ( -1 ) * jointNodeQ * sqrt(2) - bodyWidth / 2 * cos(90 deg) + ( ( 1 ) * nodeHalfWidth ) * sin(90 deg) ) + ( 0 ) * ( ( -1 ) * endNodeX - ( ( -1 ) * jointNodeQ * sqrt(2) - bodyWidth / 2 * cos(90 deg) + ( ( 1 ) * nodeHalfWidth ) * sin(90 deg) ) ) ) + ( 0 ) * ( ( 1 ) * nodeHalfWidth ))"
equation "d385 = abs(( 0 ) * ( ( ( -1 ) * jointNodeQ * sqrt(2) - bodyWidth / 2 * cos(90 deg) + ( ( 1 ) * nodeHalfWidth ) * sin(90 deg) ) + ( 0 ) * ( ( -1 ) * endNodeX - ( ( -1 ) * jointNodeQ * sqrt(2) - bodyWidth / 2 * cos(90 deg) + ( ( 1 ) * nodeHalfWidth ) * sin(90 deg) ) ) ) + ( -1 ) * ( ( 1 ) * nodeHalfWidth ))"
equation "d386 = abs(( 1 ) * ( ( ( -1 ) * jointNodeQ * sqrt(2) - bodyWidth / 2 * cos(90 deg) + ( ( -1 ) * nodeHalfWidth ) * sin(90 deg) ) + ( 0 ) * ( ( -1 ) * endNodeX - ( ( -1 ) * jointNodeQ * sqrt(2) - bodyWidth / 2 * cos(90 deg) + ( ( -1 ) * nodeHalfWidth ) * sin(90 deg) ) ) ) + ( 0 ) * ( ( -1 ) * nodeHalfWidth ))"
equation "d387 = abs(( 0 ) * ( ( ( -1 ) * jointNodeQ * sqrt(2) - bodyWidth / 2 * cos(90 deg) + ( ( -1 ) * nodeHalfWidth ) * sin(90 deg) ) + ( 0 ) * ( ( -1 ) * endNodeX - ( ( -1 ) * jointNodeQ * sqrt(2) - bodyWidth / 2 * cos(90 deg) + ( ( -1 ) * nodeHalfWidth ) * sin(90 deg) ) ) ) + ( -1 ) * ( ( -1 ) * nodeHalfWidth ))"
equation "d388 = abs(( 1 ) * ( ( ( -1 ) * jointNodeQ * sqrt(2) - bodyWidth / 2 * cos(90 deg) + ( ( 1 ) * nodeHalfWidth ) * sin(90 deg) ) + ( 0.5 ) * ( ( -1 ) * endNodeX - ( ( -1 ) * jointNodeQ * sqrt(2) - bodyWidth / 2 * cos(90 deg) + ( ( 1 ) * nodeHalfWidth ) * sin(90 deg) ) ) ) + ( 0 ) * ( ( 1 ) * nodeHalfWidth ))"
equation "d389 = abs(( 0 ) * ( ( ( -1 ) * jointNodeQ * sqrt(2) - bodyWidth / 2 * cos(90 deg) + ( ( 1 ) * nodeHalfWidth ) * sin(90 deg) ) + ( 0.5 ) * ( ( -1 ) * endNodeX - ( ( -1 ) * jointNodeQ * sqrt(2) - bodyWidth / 2 * cos(90 deg) + ( ( 1 ) * nodeHalfWidth ) * sin(90 deg) ) ) ) + ( -1 ) * ( ( 1 ) * nodeHalfWidth ))"
equation "d390 = -memberWidth / 2"
equation "d391 = -( wall + 0.2 mm )"
equation "d393 = abs(( 1 ) * ( ( ( -1 ) * jointNodeQ * sqrt(2) - bodyWidth / 2 * cos(90 deg) + ( ( -1 ) * nodeHalfWidth ) * sin(90 deg) ) + ( 0 ) * ( ( -1 ) * endNodeX - ( ( -1 ) * jointNodeQ * sqrt(2) - bodyWidth / 2 * cos(90 deg) + ( ( -1 ) * nodeHalfWidth ) * sin(90 deg) ) ) ) + ( 0 ) * ( ( -1 ) * nodeHalfWidth ))"
equation "d394 = abs(( 0 ) * ( ( ( -1 ) * jointNodeQ * sqrt(2) - bodyWidth / 2 * cos(90 deg) + ( ( -1 ) * nodeHalfWidth ) * sin(90 deg) ) + ( 0 ) * ( ( -1 ) * endNodeX - ( ( -1 ) * jointNodeQ * sqrt(2) - bodyWidth / 2 * cos(90 deg) + ( ( -1 ) * nodeHalfWidth ) * sin(90 deg) ) ) ) + ( -1 ) * ( ( -1 ) * nodeHalfWidth ))"
equation "d395 = abs(( 1 ) * ( ( ( -1 ) * jointNodeQ * sqrt(2) - bodyWidth / 2 * cos(90 deg) + ( ( 1 ) * nodeHalfWidth ) * sin(90 deg) ) + ( 0.5 ) * ( ( -1 ) * endNodeX - ( ( -1 ) * jointNodeQ * sqrt(2) - bodyWidth / 2 * cos(90 deg) + ( ( 1 ) * nodeHalfWidth ) * sin(90 deg) ) ) ) + ( 0 ) * ( ( 1 ) * nodeHalfWidth ))"
equation "d396 = abs(( 0 ) * ( ( ( -1 ) * jointNodeQ * sqrt(2) - bodyWidth / 2 * cos(90 deg) + ( ( 1 ) * nodeHalfWidth ) * sin(90 deg) ) + ( 0.5 ) * ( ( -1 ) * endNodeX - ( ( -1 ) * jointNodeQ * sqrt(2) - bodyWidth / 2 * cos(90 deg) + ( ( 1 ) * nodeHalfWidth ) * sin(90 deg) ) ) ) + ( -1 ) * ( ( 1 ) * nodeHalfWidth ))"
equation "d397 = abs(( 1 ) * ( ( ( -1 ) * jointNodeQ * sqrt(2) - bodyWidth / 2 * cos(90 deg) + ( ( -1 ) * nodeHalfWidth ) * sin(90 deg) ) + ( 1 ) * ( ( -1 ) * endNodeX - ( ( -1 ) * jointNodeQ * sqrt(2) - bodyWidth / 2 * cos(90 deg) + ( ( -1 ) * nodeHalfWidth ) * sin(90 deg) ) ) ) + ( 0 ) * ( ( -1 ) * nodeHalfWidth ))"
equation "d398 = abs(( 0 ) * ( ( ( -1 ) * jointNodeQ * sqrt(2) - bodyWidth / 2 * cos(90 deg) + ( ( -1 ) * nodeHalfWidth ) * sin(90 deg) ) + ( 1 ) * ( ( -1 ) * endNodeX - ( ( -1 ) * jointNodeQ * sqrt(2) - bodyWidth / 2 * cos(90 deg) + ( ( -1 ) * nodeHalfWidth ) * sin(90 deg) ) ) ) + ( -1 ) * ( ( -1 ) * nodeHalfWidth ))"
equation "d399 = memberWidth / 2"
equation "d400 = -( wall + 0.2 mm )"
equation "d402 = abs(( 1 ) * ( ( ( -1 ) * jointNodeQ * sqrt(2) - bodyWidth / 2 * cos(90 deg) + ( ( 1 ) * nodeHalfWidth ) * sin(90 deg) ) + ( 0.5 ) * ( ( -1 ) * endNodeX - ( ( -1 ) * jointNodeQ * sqrt(2) - bodyWidth / 2 * cos(90 deg) + ( ( 1 ) * nodeHalfWidth ) * sin(90 deg) ) ) ) + ( 0 ) * ( ( 1 ) * nodeHalfWidth ))"
equation "d403 = abs(( 0 ) * ( ( ( -1 ) * jointNodeQ * sqrt(2) - bodyWidth / 2 * cos(90 deg) + ( ( 1 ) * nodeHalfWidth ) * sin(90 deg) ) + ( 0.5 ) * ( ( -1 ) * endNodeX - ( ( -1 ) * jointNodeQ * sqrt(2) - bodyWidth / 2 * cos(90 deg) + ( ( 1 ) * nodeHalfWidth ) * sin(90 deg) ) ) ) + ( -1 ) * ( ( 1 ) * nodeHalfWidth ))"
equation "d404 = abs(( 1 ) * ( ( ( -1 ) * jointNodeQ * sqrt(2) - bodyWidth / 2 * cos(90 deg) + ( ( -1 ) * nodeHalfWidth ) * sin(90 deg) ) + ( 1 ) * ( ( -1 ) * endNodeX - ( ( -1 ) * jointNodeQ * sqrt(2) - bodyWidth / 2 * cos(90 deg) + ( ( -1 ) * nodeHalfWidth ) * sin(90 deg) ) ) ) + ( 0 ) * ( ( -1 ) * nodeHalfWidth ))"
equation "d405 = abs(( 0 ) * ( ( ( -1 ) * jointNodeQ * sqrt(2) - bodyWidth / 2 * cos(90 deg) + ( ( -1 ) * nodeHalfWidth ) * sin(90 deg) ) + ( 1 ) * ( ( -1 ) * endNodeX - ( ( -1 ) * jointNodeQ * sqrt(2) - bodyWidth / 2 * cos(90 deg) + ( ( -1 ) * nodeHalfWidth ) * sin(90 deg) ) ) ) + ( -1 ) * ( ( -1 ) * nodeHalfWidth ))"
equation "d406 = abs(( 1 ) * ( ( ( -1 ) * jointNodeQ * sqrt(2) - bodyWidth / 2 * cos(90 deg) + ( ( 1 ) * nodeHalfWidth ) * sin(90 deg) ) + ( 1 ) * ( ( -1 ) * endNodeX - ( ( -1 ) * jointNodeQ * sqrt(2) - bodyWidth / 2 * cos(90 deg) + ( ( 1 ) * nodeHalfWidth ) * sin(90 deg) ) ) ) + ( 0 ) * ( ( 1 ) * nodeHalfWidth ))"
equation "d407 = abs(( 0 ) * ( ( ( -1 ) * jointNodeQ * sqrt(2) - bodyWidth / 2 * cos(90 deg) + ( ( 1 ) * nodeHalfWidth ) * sin(90 deg) ) + ( 1 ) * ( ( -1 ) * endNodeX - ( ( -1 ) * jointNodeQ * sqrt(2) - bodyWidth / 2 * cos(90 deg) + ( ( 1 ) * nodeHalfWidth ) * sin(90 deg) ) ) ) + ( -1 ) * ( ( 1 ) * nodeHalfWidth ))"
equation "d408 = -memberWidth / 2"
equation "d409 = -( wall + 0.2 mm )"
equation "d412 = apertureRadius"
equation "d415 = bodyWidth / 2"
equation "d417 = abs(( 1 ) * ( ( ( -1 ) * jointNodeQ * sqrt(2) - bodyWidth / 2 * cos(135 deg) + ( ( -1 ) * nodeHalfWidth ) * sin(135 deg) ) + ( 0 ) * ( ( -1 ) * endNodeX - ( ( -1 ) * jointNodeQ * sqrt(2) - bodyWidth / 2 * cos(135 deg) + ( ( -1 ) * nodeHalfWidth ) * sin(135 deg) ) ) ) + ( 0 ) * ( ( -1 ) * nodeHalfWidth ))"
equation "d418 = abs(( 0 ) * ( ( ( -1 ) * jointNodeQ * sqrt(2) - bodyWidth / 2 * cos(135 deg) + ( ( -1 ) * nodeHalfWidth ) * sin(135 deg) ) + ( 0 ) * ( ( -1 ) * endNodeX - ( ( -1 ) * jointNodeQ * sqrt(2) - bodyWidth / 2 * cos(135 deg) + ( ( -1 ) * nodeHalfWidth ) * sin(135 deg) ) ) ) + ( -1 ) * ( ( -1 ) * nodeHalfWidth ))"
equation "d419 = abs(( 1 ) * ( ( ( -1 ) * jointNodeQ * sqrt(2) - bodyWidth / 2 * cos(135 deg) + ( ( 1 ) * nodeHalfWidth ) * sin(135 deg) ) + ( 0 ) * ( ( -1 ) * endNodeX - ( ( -1 ) * jointNodeQ * sqrt(2) - bodyWidth / 2 * cos(135 deg) + ( ( 1 ) * nodeHalfWidth ) * sin(135 deg) ) ) ) + ( 0 ) * ( ( 1 ) * nodeHalfWidth ))"
equation "d420 = abs(( 0 ) * ( ( ( -1 ) * jointNodeQ * sqrt(2) - bodyWidth / 2 * cos(135 deg) + ( ( 1 ) * nodeHalfWidth ) * sin(135 deg) ) + ( 0 ) * ( ( -1 ) * endNodeX - ( ( -1 ) * jointNodeQ * sqrt(2) - bodyWidth / 2 * cos(135 deg) + ( ( 1 ) * nodeHalfWidth ) * sin(135 deg) ) ) ) + ( -1 ) * ( ( 1 ) * nodeHalfWidth ))"
equation "d421 = abs(( 1 ) * ( ( ( -1 ) * jointNodeQ * sqrt(2) - bodyWidth / 2 * cos(135 deg) + ( ( -1 ) * nodeHalfWidth ) * sin(135 deg) ) + ( 0.333333333333333 ) * ( ( -1 ) * endNodeX - ( ( -1 ) * jointNodeQ * sqrt(2) - bodyWidth / 2 * cos(135 deg) + ( ( -1 ) * nodeHalfWidth ) * sin(135 deg) ) ) ) + ( 0 ) * ( ( -1 ) * nodeHalfWidth ))"
equation "d422 = abs(( 0 ) * ( ( ( -1 ) * jointNodeQ * sqrt(2) - bodyWidth / 2 * cos(135 deg) + ( ( -1 ) * nodeHalfWidth ) * sin(135 deg) ) + ( 0.333333333333333 ) * ( ( -1 ) * endNodeX - ( ( -1 ) * jointNodeQ * sqrt(2) - bodyWidth / 2 * cos(135 deg) + ( ( -1 ) * nodeHalfWidth ) * sin(135 deg) ) ) ) + ( -1 ) * ( ( -1 ) * nodeHalfWidth ))"
equation "d423 = memberWidth / 2"
equation "d424 = -( wall + 0.2 mm )"
equation "d426 = abs(( 1 ) * ( ( ( -1 ) * jointNodeQ * sqrt(2) - bodyWidth / 2 * cos(135 deg) + ( ( 1 ) * nodeHalfWidth ) * sin(135 deg) ) + ( 0 ) * ( ( -1 ) * endNodeX - ( ( -1 ) * jointNodeQ * sqrt(2) - bodyWidth / 2 * cos(135 deg) + ( ( 1 ) * nodeHalfWidth ) * sin(135 deg) ) ) ) + ( 0 ) * ( ( 1 ) * nodeHalfWidth ))"
equation "d427 = abs(( 0 ) * ( ( ( -1 ) * jointNodeQ * sqrt(2) - bodyWidth / 2 * cos(135 deg) + ( ( 1 ) * nodeHalfWidth ) * sin(135 deg) ) + ( 0 ) * ( ( -1 ) * endNodeX - ( ( -1 ) * jointNodeQ * sqrt(2) - bodyWidth / 2 * cos(135 deg) + ( ( 1 ) * nodeHalfWidth ) * sin(135 deg) ) ) ) + ( -1 ) * ( ( 1 ) * nodeHalfWidth ))"
equation "d428 = abs(( 1 ) * ( ( ( -1 ) * jointNodeQ * sqrt(2) - bodyWidth / 2 * cos(135 deg) + ( ( -1 ) * nodeHalfWidth ) * sin(135 deg) ) + ( 0.333333333333333 ) * ( ( -1 ) * endNodeX - ( ( -1 ) * jointNodeQ * sqrt(2) - bodyWidth / 2 * cos(135 deg) + ( ( -1 ) * nodeHalfWidth ) * sin(135 deg) ) ) ) + ( 0 ) * ( ( -1 ) * nodeHalfWidth ))"
equation "d429 = abs(( 0 ) * ( ( ( -1 ) * jointNodeQ * sqrt(2) - bodyWidth / 2 * cos(135 deg) + ( ( -1 ) * nodeHalfWidth ) * sin(135 deg) ) + ( 0.333333333333333 ) * ( ( -1 ) * endNodeX - ( ( -1 ) * jointNodeQ * sqrt(2) - bodyWidth / 2 * cos(135 deg) + ( ( -1 ) * nodeHalfWidth ) * sin(135 deg) ) ) ) + ( -1 ) * ( ( -1 ) * nodeHalfWidth ))"
equation "d430 = abs(( 1 ) * ( ( ( -1 ) * jointNodeQ * sqrt(2) - bodyWidth / 2 * cos(135 deg) + ( ( 1 ) * nodeHalfWidth ) * sin(135 deg) ) + ( 0.666666666666667 ) * ( ( -1 ) * endNodeX - ( ( -1 ) * jointNodeQ * sqrt(2) - bodyWidth / 2 * cos(135 deg) + ( ( 1 ) * nodeHalfWidth ) * sin(135 deg) ) ) ) + ( 0 ) * ( ( 1 ) * nodeHalfWidth ))"
equation "d431 = abs(( 0 ) * ( ( ( -1 ) * jointNodeQ * sqrt(2) - bodyWidth / 2 * cos(135 deg) + ( ( 1 ) * nodeHalfWidth ) * sin(135 deg) ) + ( 0.666666666666667 ) * ( ( -1 ) * endNodeX - ( ( -1 ) * jointNodeQ * sqrt(2) - bodyWidth / 2 * cos(135 deg) + ( ( 1 ) * nodeHalfWidth ) * sin(135 deg) ) ) ) + ( -1 ) * ( ( 1 ) * nodeHalfWidth ))"
equation "d432 = -memberWidth / 2"
equation "d433 = -( wall + 0.2 mm )"
equation "d435 = abs(( 1 ) * ( ( ( -1 ) * jointNodeQ * sqrt(2) - bodyWidth / 2 * cos(135 deg) + ( ( -1 ) * nodeHalfWidth ) * sin(135 deg) ) + ( 0.333333333333333 ) * ( ( -1 ) * endNodeX - ( ( -1 ) * jointNodeQ * sqrt(2) - bodyWidth / 2 * cos(135 deg) + ( ( -1 ) * nodeHalfWidth ) * sin(135 deg) ) ) ) + ( 0 ) * ( ( -1 ) * nodeHalfWidth ))"
equation "d436 = abs(( 0 ) * ( ( ( -1 ) * jointNodeQ * sqrt(2) - bodyWidth / 2 * cos(135 deg) + ( ( -1 ) * nodeHalfWidth ) * sin(135 deg) ) + ( 0.333333333333333 ) * ( ( -1 ) * endNodeX - ( ( -1 ) * jointNodeQ * sqrt(2) - bodyWidth / 2 * cos(135 deg) + ( ( -1 ) * nodeHalfWidth ) * sin(135 deg) ) ) ) + ( -1 ) * ( ( -1 ) * nodeHalfWidth ))"
equation "d437 = abs(( 1 ) * ( ( ( -1 ) * jointNodeQ * sqrt(2) - bodyWidth / 2 * cos(135 deg) + ( ( 1 ) * nodeHalfWidth ) * sin(135 deg) ) + ( 0.666666666666667 ) * ( ( -1 ) * endNodeX - ( ( -1 ) * jointNodeQ * sqrt(2) - bodyWidth / 2 * cos(135 deg) + ( ( 1 ) * nodeHalfWidth ) * sin(135 deg) ) ) ) + ( 0 ) * ( ( 1 ) * nodeHalfWidth ))"
equation "d438 = abs(( 0 ) * ( ( ( -1 ) * jointNodeQ * sqrt(2) - bodyWidth / 2 * cos(135 deg) + ( ( 1 ) * nodeHalfWidth ) * sin(135 deg) ) + ( 0.666666666666667 ) * ( ( -1 ) * endNodeX - ( ( -1 ) * jointNodeQ * sqrt(2) - bodyWidth / 2 * cos(135 deg) + ( ( 1 ) * nodeHalfWidth ) * sin(135 deg) ) ) ) + ( -1 ) * ( ( 1 ) * nodeHalfWidth ))"